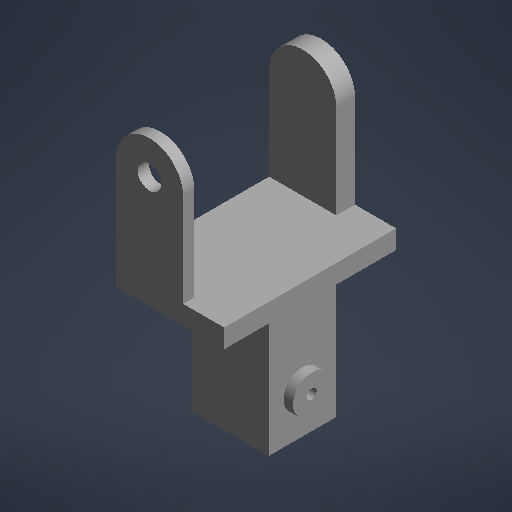
# Autodesk Inventor part: R2_brazo_der
Saved by Autodesk Inventor 2027 (Build 310192060, 192F)
## iProperties
Part Number: R2_brazo_der
Material: Genérico
Document SubType Name: Modelado
Designer: rodri
Appearance: Por defecto
Author: rodri
Autodesk Inventor part; units mm, degrees
ref_plane "Plano de trabajo1" through (0, 0, -9) normal (0, 0, 1) x (1, 0, 0)
sketch "Boceto1" plane through (0, 0, -9) normal (0, 0, 1) x (1, 0, 0)
  line L0 (-87.1, -10.1) -> (-66.5, -10.1)
  line L1 (-66.5, -10.1) -> (-66.5, 23.1)
  line L2 (-66.5, 23.1) -> (-87.1, 23.1)
  line L3 (-87.1, 23.1) -> (-87.1, -10.1)
  constraints: 8 end point, 2 parallel, 1 horizontal, 1 perpendicular
extrude "Extrusión1" add sketch "Boceto1" along normal blind 18
ref_plane "Plano de trabajo2" through (0, 0, -6.5) normal (0, 0, 1) x (1, 0, 0)
sketch "Boceto2" plane through (0, 0, -6.5) normal (0, 0, 1) x (1, 0, 0)
  line L0 (-87.2, -5.3) -> (-69, -5.3)
  line L1 (-69, -5.3) -> (-69, 18.3)
  line L2 (-69, 18.3) -> (-87.2, 18.3)
  line L3 (-87.2, 18.3) -> (-87.2, -5.3)
  constraints: 8 end point, 2 parallel, 1 horizontal, 1 perpendicular
extrude "Extrusión2" cut sketch "Boceto2" along normal blind 13
ref_plane "Plano de trabajo3" through (0, 0, -3.5) normal (0, 0, 1) x (1, 0, 0)
sketch "Boceto3" plane through (0, 0, -3.5) normal (0, 0, 1) x (1, 0, 0)
  line L0 (-74, 16.5) -> (-69, 16.5)
  line L1 (-69, 16.5) -> (-69, 23.5)
  line L2 (-69, 23.5) -> (-74, 23.5)
  line L3 (-74, 23.5) -> (-74, 16.5)
  constraints: 8 end point, 2 parallel, 1 horizontal, 1 perpendicular
extrude "Extrusión3" cut sketch "Boceto3" along normal blind 7
ref_plane "Plano de trabajo4" through (-87.2, 0, 0) normal (1, 0, 0) x (0, 1, 0)
sketch "Boceto4" plane through (-87.2, 0, 0) normal (1, 0, 0) x (0, 1, 0)
  circle A0 centre (20.4, 0) radius 0.85
  constraints: 1 centre point
extrude "Extrusión4" cut sketch "Boceto4" along normal blind 6.1
ref_plane "Plano de trabajo5" through (-87.2, 0, 0) normal (1, 0, 0) x (0, 1, 0)
sketch "Boceto5" plane through (-87.2, 0, 0) normal (1, 0, 0) x (0, 1, 0)
  circle A0 centre (-7.4, 0) radius 0.85
  constraints: 1 centre point
extrude "Extrusión5" cut sketch "Boceto5" along normal blind 6.1
ref_plane "Plano de trabajo6" through (-66.51, 0, 0) normal (1, 0, 0) x (0, 1, 0)
sketch "Boceto6" plane through (-66.51, 0, 0) normal (1, 0, 0) x (0, 1, 0)
  circle A0 centre (1, 0) radius 5
  constraints: 1 centre point
extrude "Extrusión6" add sketch "Boceto6" along normal blind 2.51
ref_plane "Plano de trabajo7" through (-68.4, 0, 0) normal (1, 0, 0) x (0, 1, 0)
sketch "Boceto7" plane through (-68.4, 0, 0) normal (1, 0, 0) x (0, 1, 0)
  circle A0 centre (1, 0) radius 1.3
  constraints: 1 centre point
extrude "Extrusión7" cut sketch "Boceto7" along normal blind 4.5
ref_plane "Plano de trabajo8" through (0, 0, -22.6) normal (0, 0, 1) x (1, 0, 0)
sketch "Boceto8" plane through (0, 0, -22.6) normal (0, 0, 1) x (1, 0, 0)
  line L0 (-93, 23.09) -> (-75, 23.09)
  line L1 (-75, 23.09) -> (-75, 53)
  line L2 (-75, 53) -> (-93, 53)
  line L3 (-93, 53) -> (-93, 23.09)
  constraints: 8 end point, 2 parallel, 1 horizontal, 1 perpendicular
extrude "Extrusión8" add sketch "Boceto8" along normal blind 4.99
ref_plane "Plano de trabajo9" through (0, 0, -22.6) normal (0, 0, 1) x (1, 0, 0)
sketch "Boceto9" plane through (0, 0, -22.6) normal (0, 0, 1) x (1, 0, 0)
  circle A0 centre (-84, 53) radius 9
  constraints: 1 centre point
extrude "Extrusión9" add sketch "Boceto9" along normal blind 4.99
ref_plane "Plano de trabajo10" through (0, 0, 20.41) normal (0, 0, 1) x (1, 0, 0)
sketch "Boceto10" plane through (0, 0, 20.41) normal (0, 0, 1) x (1, 0, 0)
  line L0 (-93, 23.09) -> (-75, 23.09)
  line L1 (-75, 23.09) -> (-75, 53)
  line L2 (-75, 53) -> (-93, 53)
  line L3 (-93, 53) -> (-93, 23.09)
  constraints: 8 end point, 2 parallel, 1 horizontal, 1 perpendicular
extrude "Extrusión10" add sketch "Boceto10" along normal blind 3
ref_plane "Plano de trabajo11" through (0, 0, 20.41) normal (0, 0, 1) x (1, 0, 0)
sketch "Boceto11" plane through (0, 0, 20.41) normal (0, 0, 1) x (1, 0, 0)
  circle A0 centre (-84, 53) radius 9
  constraints: 1 centre point
extrude "Extrusión11" add sketch "Boceto11" along normal blind 3
ref_plane "Plano de trabajo12" through (0, 0, -22.6) normal (0, 0, 1) x (1, 0, 0)
sketch "Boceto12" plane through (0, 0, -22.6) normal (0, 0, 1) x (1, 0, 0)
  line L0 (-93, 23.09) -> (-64, 23.09)
  line L1 (-64, 23.09) -> (-64, 28.1)
  line L2 (-64, 28.1) -> (-93, 28.1)
  line L3 (-93, 28.1) -> (-93, 23.09)
  constraints: 8 end point, 2 parallel, 1 horizontal, 1 perpendicular
extrude "Extrusión12" add sketch "Boceto12" along normal blind 46
ref_plane "Plano de trabajo13" through (0, 0, -22.7) normal (0, 0, 1) x (1, 0, 0)
sketch "Boceto13" plane through (0, 0, -22.7) normal (0, 0, 1) x (1, 0, 0)
  circle A0 centre (-84, 53) radius 4.2
  constraints: 1 centre point
extrude "Extrusión13" cut sketch "Boceto13" along normal blind 3.2
ref_plane "Plano de trabajo14" through (0, 0, 20.3) normal (0, 0, 1) x (1, 0, 0)
sketch "Boceto14" plane through (0, 0, 20.3) normal (0, 0, 1) x (1, 0, 0)
  circle A0 centre (-84, 53) radius 3.15
  constraints: 1 centre point
extrude "Extrusión14" cut sketch "Boceto14" along normal blind 3.2
